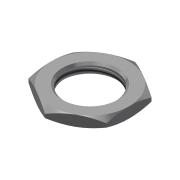
# Autodesk Inventor part: nut
Saved by Autodesk Inventor 2015 SP1 (Build 190203100, 203)
## iProperties
Created: 2015-06-28
Part Number: nut
Material: Generic
Document SubType Name: Modeling
Designer: Peter Mulkers
Density: 1 g/cm^3
Appearance: Steel - Polished
Author: Peter Mulkers
Autodesk Inventor part; units mm, degrees
ref_plane "YZ Plane" through (0, 0, 0) normal (1, 0, 0) x (0, 1, 0)
ref_plane "XZ Plane" through (0, 0, 0) normal (0, 1, 0) x (-1, 0, 0)
ref_plane "XY Plane" through (0, 0, 0) normal (0, 0, 1) x (1, 0, 0)
sketch "Sketch1" plane through (0, 0, 0) normal (0, 0, 1) x (1, 0, 0)
  line L0 (0, 6.3509) -> (5.5, 3.1754)
  line L1 (5.5, 3.1754) -> (5.5, -3.1754)
  line L2 (5.5, -3.1754) -> (0, -6.3509)
  line L3 (0, -6.3509) -> (-5.5, -3.1754)
  line L4 (-5.5, -3.1754) -> (-5.5, 3.1754)
  line L5 (-5.5, 3.1754) -> (0, 6.3509)
  point P0 (0, 0)
  point P1 (0, 0)
  dimension "d0" = 11
  constraints: 12 end point, 1 coincident, 13 other
  measures "d0" distance between parallel lines of L2 L5
extrude "Extrusion1" add sketch "Sketch1" along normal mid plane 1.5
sketch "Sketch2" plane through (0, 0, 0.75) normal (0, 0, 1) x (1, 0, 0)
  point P0 (0, 0)
  point P1 (0, 0)
  constraints: 2 coincident
hole "Hole1" at (0, 0, 0.75) direction (0, 0, -1) diameter 7.188 end through all thread size "M8x0.75" class "6H" standard "ISO Metric profile"
chamfer "Chamfer1" distance 0.3 angle 45 2 edges at (0, 3.594, 0.75) (0, 3.594, -0.75)
sketch "Sketch4" plane through (0, 0, 0) normal (1, 0, 0) x (0, 1, 0)
  line L0 (6.3509, 0.75) -> (5.5, 0.75)
  line L1 (5.5, 0.75) -> (6.3509, 0.2588)
  line L2 (5.5, 0.75) -> (6.4825, 0.75) construction
  line L3 (6.3509, 0.75) -> (6.3509, 0.2588)
  line L4 (-1.1786, 0) -> (7.0718, 0) construction
  line L5 (6.3509, -0.75) -> (5.5, -0.75)
  line L6 (5.5, -0.75) -> (6.3509, -0.2588)
  line L7 (6.3509, -0.75) -> (6.3509, -0.2588)
  line L8 (0, -1.05) -> (0, 1.05) projected
  point P0 (0, 0)
  dimension "d13" = 5.5
  dimension "d14" = 30
  constraints: 14 end point, 3 symmetric about line, 2 horizontal, 1 equal length, 1 perpendicular, 1 vertical alignment
  measures "d13" horizontal distance of point (0, 0) L0.end
  measures "d14" angle of L1 L2
revolve "Revolution1" cut sketch "Sketch4" angle 360 about axis through (0, 0, -10) along (0, 0, 1)
body "Solid1"
